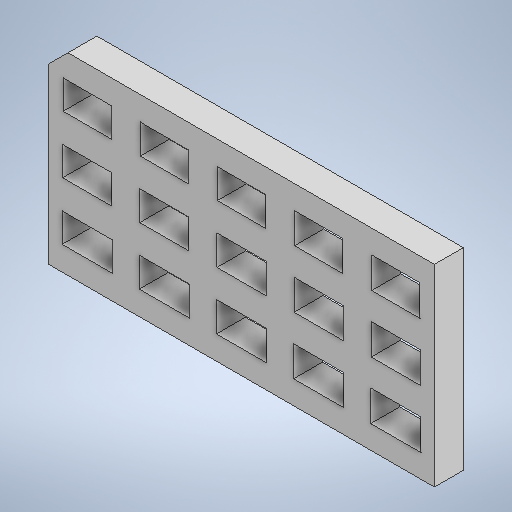
# Autodesk Inventor part: ShaftSizeGauge1
Saved by Autodesk Inventor 2025.3 (Build 293356000, 356)
## iProperties
Created: 2025-09-02
Part Number: ShaftSizeGauge1
Material: 一般
Document SubType Name: Modeling
Designer: yamashita1
Density: 1 g/cm^3
Appearance: 既定
Author: yamashita1
Autodesk Inventor part; units mm, degrees
ref_plane "YZ Plane" through (0, 0, 0) normal (1, 0, 0) x (0, 1, 0)
ref_plane "XZ Plane" through (0, 0, 0) normal (0, 1, 0) x (-1, 0, 0)
ref_plane "XY Plane" through (0, 0, 0) normal (0, 0, 1) x (1, 0, 0)
sketch "スケッチ1" plane through (0, 0, 0) normal (0, 0, 1) x (1, 0, 0)
  line L0 (-20, 10) -> (20, 10)
  line L1 (20, 10) -> (20, -10)
  line L2 (20, -10) -> (-20, -10)
  line L3 (-20, -10) -> (-20, 10)
  point P0 (0, 0)
  point P1 (0, 10)
  point P2 (-20, 0)
  dimension "d0" = 40
  dimension "d1" = 20
  constraints: 8 end point, 2 midpoint, 2 parallel, 1 horizontal, 1 horizontal alignment, 1 perpendicular, 1 vertical alignment
  measures "d0" distance of L1.end L2.end
  measures "d1" distance of L0.end L1.end
extrude "ベース" add sketch "スケッチ1" along normal blind 3
sketch "スケッチ2" plane through (0, 0, 3) normal (0, 0, 1) x (1, 0, 0)
  line L0 (0, 8.2317) -> (0, -8.2317) construction
  line L1 (-8, -9.1471) -> (-8, 9.1471) construction
  line L2 (-16, 9.1471) -> (-16, -9.1471) construction
  line L3 (8, 9.1471) -> (8, -9.1471) construction
  line L4 (16, -9.1471) -> (16, 9.1471) construction
  line L5 (-23.0448, 0) -> (23.0448, 0) construction
  line L6 (-18.55, 1.5) -> (-13.45, 1.5)
  line L7 (-13.45, 1.5) -> (-13.45, -1.5)
  line L8 (-13.45, -1.5) -> (-18.55, -1.5)
  line L9 (-18.55, -1.5) -> (-18.55, 1.5)
  line L10 (-10.55, 1.525) -> (-5.45, 1.525)
  line L11 (-5.45, 1.525) -> (-5.45, -1.525)
  line L12 (-5.45, -1.525) -> (-10.55, -1.525)
  line L13 (-10.55, -1.525) -> (-10.55, 1.525)
  line L14 (-2.55, 1.55) -> (2.55, 1.55)
  line L15 (2.55, 1.55) -> (2.55, -1.55)
  line L16 (2.55, -1.55) -> (-2.55, -1.55)
  line L17 (-2.55, -1.55) -> (-2.55, 1.55)
  line L18 (5.45, 1.575) -> (10.55, 1.575)
  line L19 (10.55, 1.575) -> (10.55, -1.575)
  line L20 (10.55, -1.575) -> (5.45, -1.575)
  line L21 (5.45, -1.575) -> (5.45, 1.575)
  line L22 (13.45, 1.6) -> (18.55, 1.6)
  line L23 (18.55, 1.6) -> (18.55, -1.6)
  line L24 (18.55, -1.6) -> (13.45, -1.6)
  line L25 (13.45, -1.6) -> (13.45, 1.6)
  line L26 (-23.963, 6) -> (23.963, 6) construction
  line L27 (23.963, -6) -> (-23.963, -6) construction
  line L28 (-18.5, 7.5) -> (-13.5, 7.5)
  line L29 (-13.5, 7.5) -> (-13.5, 4.5)
  line L30 (-13.5, 4.5) -> (-18.5, 4.5)
  line L31 (-18.5, 4.5) -> (-18.5, 7.5)
  line L32 (-10.5, 7.525) -> (-5.5, 7.525)
  line L33 (-5.5, 7.525) -> (-5.5, 4.475)
  line L34 (-5.5, 4.475) -> (-10.5, 4.475)
  line L35 (-10.5, 4.475) -> (-10.5, 7.525)
  line L36 (-2.5, 7.525) -> (2.5, 7.525)
  line L37 (2.5, 7.525) -> (2.5, 4.475)
  line L38 (2.5, 4.475) -> (-2.5, 4.475)
  line L39 (-2.5, 4.475) -> (-2.5, 7.525)
  line L40 (13.5, 7.6) -> (18.5, 7.6)
  line L41 (18.5, 7.6) -> (18.5, 4.4)
  line L42 (18.5, 4.4) -> (13.5, 4.4)
  line L43 (13.5, 4.4) -> (13.5, 7.6)
  line L44 (5.5, 4.425) -> (10.5, 4.425)
  line L45 (10.5, 4.425) -> (10.5, 7.575)
  line L46 (10.5, 7.575) -> (5.5, 7.575)
  line L47 (5.5, 7.575) -> (5.5, 4.425)
  line L48 (-18.6, -4.5) -> (-13.4, -4.5)
  line L49 (-13.4, -4.5) -> (-13.4, -7.5)
  line L50 (-13.4, -7.5) -> (-18.6, -7.5)
  line L51 (-18.6, -7.5) -> (-18.6, -4.5)
  line L52 (-10.6, -4.475) -> (-5.4, -4.475)
  line L53 (-5.4, -4.475) -> (-5.4, -7.525)
  line L54 (-5.4, -7.525) -> (-10.6, -7.525)
  line L55 (-10.6, -7.525) -> (-10.6, -4.475)
  line L56 (-2.6, -4.45) -> (2.6, -4.45)
  line L57 (2.6, -4.45) -> (2.6, -7.55)
  line L58 (2.6, -7.55) -> (-2.6, -7.55)
  line L59 (-2.6, -7.55) -> (-2.6, -4.45)
  line L60 (5.4, -4.425) -> (10.6, -4.425)
  line L61 (10.6, -4.425) -> (10.6, -7.575)
  line L62 (10.6, -7.575) -> (5.4, -7.575)
  line L63 (5.4, -7.575) -> (5.4, -4.425)
  line L64 (13.4, -4.4) -> (18.6, -4.4)
  line L65 (18.6, -4.4) -> (18.6, -7.6)
  line L66 (18.6, -7.6) -> (13.4, -7.6)
  line L67 (13.4, -7.6) -> (13.4, -4.4)
  point P0 (0, 0)
  point P1 (0, 0)
  point P2 (8, 0)
  point P3 (16, 0)
  point P4 (-8, 0)
  point P5 (-16, 0)
  point P6 (-18.55, 0)
  point P7 (-16, 1.5)
  point P8 (-10.55, 0)
  point P9 (-8, 1.525)
  point P10 (-2.55, 0)
  point P11 (0, 1.55)
  point P12 (5.45, 0)
  point P13 (8, 1.575)
  point P14 (13.45, 0)
  point P15 (16, 1.6)
  point P16 (0, 6)
  point P17 (0, -6)
  point P18 (0, 7.525)
  point P19 (-2.5, 6)
  point P20 (-8, 7.525)
  point P21 (-10.5, 6)
  point P22 (-16, 7.5)
  point P23 (-18.5, 6)
  point P24 (16, 7.6)
  point P25 (13.5, 6)
  point P26 (8, 7.575)
  point P27 (5.5, 6)
  point P28 (-16, -4.5)
  point P29 (-18.6, -6)
  point P30 (-8, -4.475)
  point P31 (-10.6, -6)
  point P32 (0, -4.45)
  point P33 (-2.6, -6)
  point P34 (8, -4.425)
  point P35 (5.4, -6)
  point P36 (16, -4.4)
  point P37 (13.4, -6)
  dimension "d4" = 8
  dimension "d5" = 8
  dimension "d6" = 5.1
  dimension "d7" = 3.1
  dimension "d8" = 6
  dimension "d9" = 3.05
  dimension "d10" = 3
  dimension "d11" = 3.15
  dimension "d12" = 3.2
  dimension "d13" = 5
  dimension "d14" = 5.2
  constraints: 134 end point, 37 midpoint, 31 parallel, 28 point on line, 21 equal length, 16 horizontal, 15 perpendicular, 2 vertical, 1 coincident, 15 other
  measures "d4" distance between parallel lines of L0 L1
  measures "d5" distance between parallel lines of L2 L1
  measures "d6" distance of L15.end L16.end
  measures "d7" distance of L14.end L15.end
  measures "d8" distance of the line from the sketch origin of L26
  measures "d9" distance of L10.end L11.end
  measures "d10" distance of L6.end L7.end
  measures "d11" distance of L18.end L19.end
  measures "d12" distance of L22.end L23.end
  measures "d13" distance of L37.end L38.end
  measures "d14" distance of L57.end L58.end
extrude "押し出し2" cut sketch "スケッチ2" against normal blind 3
chamfer "面取り1" distance 2 angle 45 1 edges at (-20, 10, 1.5)
equation "\"d5\" = d4"
